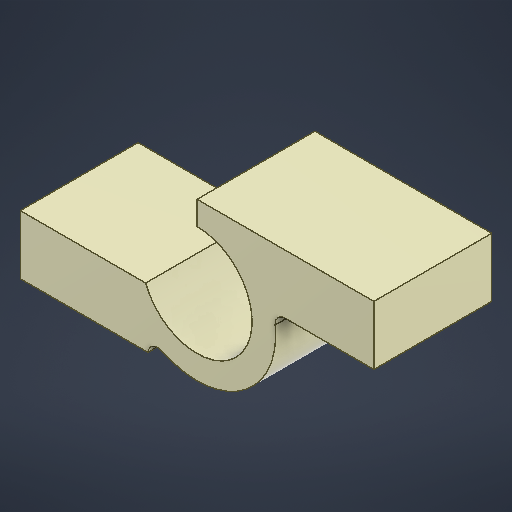
# Autodesk Inventor part: EHR_MOLA_TORCAO
Saved by Autodesk Inventor 2027.1 (Build 311270010, 270A)
## iProperties
Created: 2026-11-20
Part Number: EHR_MOLA_TORCAO
Material: PP impresso 3D
Document SubType Name: Modeling
Designer: Ailton Soares
Mass: 0.447122 g
Surface Area: 5.0015 cm^2
Volume: 0.496802 cm^3
Density: 0.9 g/cm^3
Appearance: Smooth - Ash
Author: Ailton Soares
Autodesk Inventor part; units mm, degrees
ref_plane "YZ Plane" through (0, 0, 0) normal (1, 0, 0) x (0, 1, 0)
ref_plane "XZ Plane" through (0, 0, 0) normal (0, 1, 0) x (-1, 0, 0)
ref_plane "XY Plane" through (0, 0, 0) normal (0, 0, 1) x (1, 0, 0)
sketch "Sketch1_Perfil" plane through (0, 0, 0) normal (0, 0, 1) x (1, 0, 0)
  line L0 (0, 0) -> (6.5, 0)
  line L1 (6.5, 0) -> (6.5, 3)
  line L2 (6.5, 3) -> (0, 3)
  line L3 (0, 3) -> (0, 0)
  circle A0 centre (9, 4) radius 4
  line L4 (9, 5) -> (18, 5)
  line L5 (18, 5) -> (18, 8)
  line L6 (18, 8) -> (9, 8)
  line L7 (9, 8) -> (9, 5)
  dimension "d0" = 6.5
  dimension "d1" = 3
  dimension "d2" = 9
  dimension "d3" = 4
  dimension "d4" = 8
  dimension "d5" = 8
  dimension "d6" = 3
  dimension "d7" = 18
  constraints: 16 end point, 4 parallel, 2 horizontal, 2 perpendicular, 1 centre point, 1 coincident, 1 vertical alignment
  measures "d0" distance of L0.start L0.end
  measures "d1" distance of L0.start L2.end
  measures "d2" horizontal distance of point (0, 0) A0.centre
  measures "d3" vertical distance of point (0, 0) A0.centre
  measures "d4" diameter of A0
  measures "d5" vertical distance of point (0, 0) L6.end
  measures "d6" distance of L4.start L6.end
  measures "d7" horizontal distance of point (0, 0) L5.end
extrude "Extrude1_Corpo" add sketch "Sketch1_Perfil" along normal blind 6
sketch "Sketch2_Furo" plane through (0, 0, 0) normal (0, 0, 1) x (1, 0, 0)
  circle A0 centre (9, 4) radius 2.8
  point P0 (0, 0)
  dimension "d10" = 9
  dimension "d11" = 4
  dimension "d12" = 5.6
  constraints: 1 centre point
  measures "d10" horizontal distance of point (0, 0) A0.centre
  measures "d11" vertical distance of point (0, 0) A0.centre
  measures "d12" diameter of A0
extrude "Furo_Anel" cut sketch "Sketch2_Furo" along normal through all both and the other way through all
sketch "Sketch3_Abertura_C" plane through (0, 0, 0) normal (0, 0, 1) x (1, 0, 0)
  line L0 (3, 3) -> (9, 3)
  line L1 (9, 3) -> (9, 9)
  line L2 (9, 9) -> (3, 9)
  line L3 (3, 9) -> (3, 3)
  point P0 (0, 0)
  dimension "d15" = 9
  dimension "d16" = 3
  dimension "d17" = 3
  dimension "d18" = 9
  constraints: 8 end point, 2 parallel, 1 horizontal, 1 perpendicular
  measures "d15" horizontal distance of point (0, 0) L0.end
  measures "d16" horizontal distance of point (0, 0) L0.start
  measures "d17" horizontal distance of point (0, 0) L0.start
  measures "d18" vertical distance of point (0, 0) L2.end
extrude "Abertura_C" cut sketch "Sketch3_Abertura_C" along normal through all both and the other way through all
fillet "Fillet_Juncoes" radius 0.5 2 edges at (6.5, 0.8775, 3) (12.873, 5, 3)
equation "\"d0\" = x_fixa"
equation "\"d1\" = t_aba"
equation "\"d2\" = x_pino"
equation "\"d3\" = y_pino"
equation "\"d4\" = D_ext"
equation "\"d5\" = H_max"
equation "\"d6\" = t_aba"
equation "\"d7\" = L_total"
equation "\"d8\" = b"
equation "\"d10\" = x_pino"
equation "\"d11\" = y_pino"
equation "\"d12\" = D_int"
equation "\"d15\" = x_pino"
equation "\"d16\" = t_aba"
equation "\"d21\" = r_fil"
equation "\"L_total\" = 18"
equation "\"H_max\" = 8"
equation "\"b\" = 6"
equation "\"t_aba\" = 3"
equation "\"D_ext\" = H_max"
equation "\"t_anel\" = 1.2"
equation "\"D_int\" = D_ext - 2 * t_anel"
equation "\"x_pino\" = 9"
equation "\"y_pino\" = 0.5 * D_ext"
equation "\"x_fixa\" = 6.5"
equation "\"r_fil\" = 0.5"
body "Solid1"
